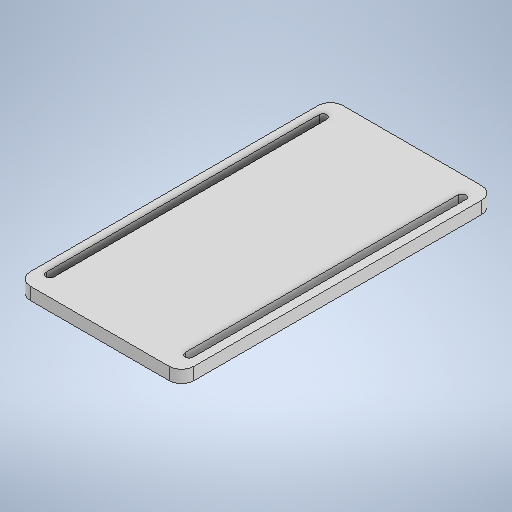
# Autodesk Inventor part: 内轴承支架1
Saved by Autodesk Inventor 2025 (Build 290162000, 162)
## iProperties
Created: 2026-11-18
Part Number: 内轴承支架1
Material: 常规
Document SubType Name: Modeling
Designer: ylh00
Density: 1 g/cm^3
Appearance: 默认
Author: ylh00
Autodesk Inventor part; units mm, degrees
ref_plane "YZ Plane" through (0, 0, 0) normal (1, 0, 0) x (0, 1, 0)
ref_plane "XZ Plane" through (0, 0, 0) normal (0, 1, 0) x (-1, 0, 0)
ref_plane "XY Plane" through (0, 0, 0) normal (0, 0, 1) x (1, 0, 0)
sketch "草图1" plane through (0, 0, 0) normal (0, 1, 0) x (-1, 0, 0)
  circle A0 centre (0, 0) radius 20
  circle A1 centre (0, 0) radius 8.1
  dimension "d0" = 40
  dimension "d1" = 16.2
  constraints: 2 centre point, 2 coincident
  measures "d0" diameter of A0
  measures "d1" diameter of A1
extrude "拉伸1" add sketch "草图1" along normal blind 9
sketch "草图2" plane through (0, 9, 0) normal (0, 1, 0) x (1, 0, 0)
  line L0 (-33, -60) -> (33, -60)
  line L1 (33, -60) -> (33, 60)
  line L2 (33, 60) -> (-33, 60)
  line L3 (-33, 60) -> (-33, -60)
  line L4 (-33, -60) -> (33, 60) construction
  line L5 (33, -60) -> (-33, 60) construction
  point P0 (0, 0)
  dimension "d4" = 120
  dimension "d17" = 66
  constraints: 12 end point, 2 midpoint, 2 parallel, 1 horizontal, 1 perpendicular
  measures "d4" distance of L1.end L0.end
  measures "d17" distance of L1.end L2.end
extrude "拉伸2" add sketch "草图2" along normal blind 5
fillet "圆角1" radius 5 1 edges at (20, 9, 0)
sketch "草图6" plane through (0, 9, 0) normal (0, -1, 0) x (1, 0, 0)
  line L0 (26.4, 55) -> (26.4, -55)
  line L1 (29.6, -55) -> (29.6, 55)
  arc A0 (29.6, 55) -> (26.4, 55) centre (28, 55) ccw
  arc A1 (26.4, -55) -> (29.6, -55) centre (28, -55) ccw
  line L2 (0, 0) -> (0, -27.6454)
  line L3 (-26.4, 55) -> (-26.4, -55)
  line L4 (-29.6, -55) -> (-29.6, 55)
  arc A2 (-26.4, 55) -> (-29.6, 55) centre (-28, 55) ccw
  arc A3 (-29.6, -55) -> (-26.4, -55) centre (-28, -55) ccw
  constraints: 10 end point, 8 point on circle, 6 symmetric about line, 4 centre point, 1 parallel, 1 vertical, 2 other
extrude "拉伸4" cut sketch "草图6" against normal blind 5
thicken "加厚1" operation add thickness 3 both sides no extend neighbours no toward (0, 0, -1) faces at (11, 10.6667, -60)
thicken "加厚2" operation add thickness 3 both sides no extend neighbours no toward (0, 0, 1) faces at (-11, 10.6667, 60)
fillet "圆角2" radius 5 4 edges at (33, 11.5, 63) (-33, 11.5, 63) (-33, 11.5, -63) (33, 11.5, -63)
sketch "草图7" plane through (0, 9, 0) normal (0, -1, 0) x (1, 0, 0)
  line L0 (-29.6, 55) -> (-29.6, -55) projected
  line L1 (-29.6, 0) -> (-26.4, 0)
  line L2 (-26.4, -55) -> (-26.4, 55) projected
  line L3 (-25, -55) -> (-25, 55)
  line L4 (-31, 55) -> (-31, -55)
  line L5 (-31, -55) -> (-25, 55) construction
  line L6 (-25, -55) -> (-31, 55) construction
  circle A0 centre (-28, 55) radius 3
  circle A1 centre (-28, -55) radius 3
  line L7 (0, 0) -> (0, 4.6843)
  line L8 (29.6, 55) -> (29.6, -55)
  line L9 (29.6, 0) -> (26.4, 0)
  line L10 (26.4, -55) -> (26.4, 55)
  line L11 (25, -55) -> (25, 55)
  line L12 (31, 55) -> (31, -55)
  line L13 (31, -55) -> (25, 55) construction
  line L14 (25, -55) -> (31, 55) construction
  circle A2 centre (28, 55) radius 3
  circle A3 centre (28, -55) radius 3
  point P0 (-28, 0)
  point P1 (28, 0)
  point P2 (26.4, 52.4623)
  point P3 (29.6, 52.4623)
  point P4 (29.6, -52.4623)
  point P5 (26.4, -52.4623)
  point P6 (-26.4, -52.4623)
  point P7 (-29.6, -52.4623)
  point P8 (-29.6, 52.4623)
  point P9 (-26.4, 52.4623)
  constraints: 26 end point, 13 symmetric about line, 7 midpoint, 3 vertical, 1 parallel, 12 other
extrude "拉伸5" cut sketch "草图7" against normal blind 1.5 contours L0 A1 L4 A0 | A0 | A0 L3 A1 L2 | A1 | A2 L12 A3 L8 | A2 | L10 A3 L11 A2 | A3
